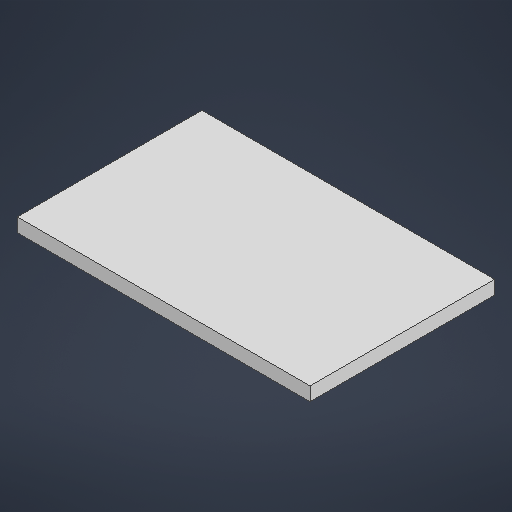
# Autodesk Inventor part: case
Saved by Autodesk Inventor 2027.1 (Build 311270010, 270A)
## iProperties
Created: 2026-11-19
Part Number: case
Material: Generic
Document SubType Name: Modeling
Designer: User
Density: 1 g/cm^3
Appearance: Default
Author: User
Autodesk Inventor part; units mm, degrees
ref_plane "YZ Plane" through (0, 0, 0) normal (1, 0, 0) x (0, 1, 0)
ref_plane "XZ Plane" through (0, 0, 0) normal (0, 1, 0) x (-1, 0, 0)
ref_plane "XY Plane" through (0, 0, 0) normal (0, 0, 1) x (1, 0, 0)
sketch "Sketch1" plane through (0, 0, 0) normal (0, 1, 0) x (-1, 0, 0)
  line L0 (-10.6832, 6.7382) -> (10.6832, 6.7382)
  line L1 (10.6832, 6.7382) -> (10.6832, -6.7382)
  line L2 (10.6832, -6.7382) -> (-10.6832, -6.7382)
  line L3 (-10.6832, -6.7382) -> (-10.6832, 6.7382)
  line L4 (-10.6832, 6.7382) -> (10.6832, -6.7382) construction
  line L5 (10.6832, 6.7382) -> (-10.6832, -6.7382) construction
  point P0 (0, 0)
  constraints: 12 end point, 2 midpoint, 2 parallel, 1 horizontal, 1 perpendicular
extrude "Extrusion1" add sketch "Sketch1" along normal blind 1
body "Solid1"
